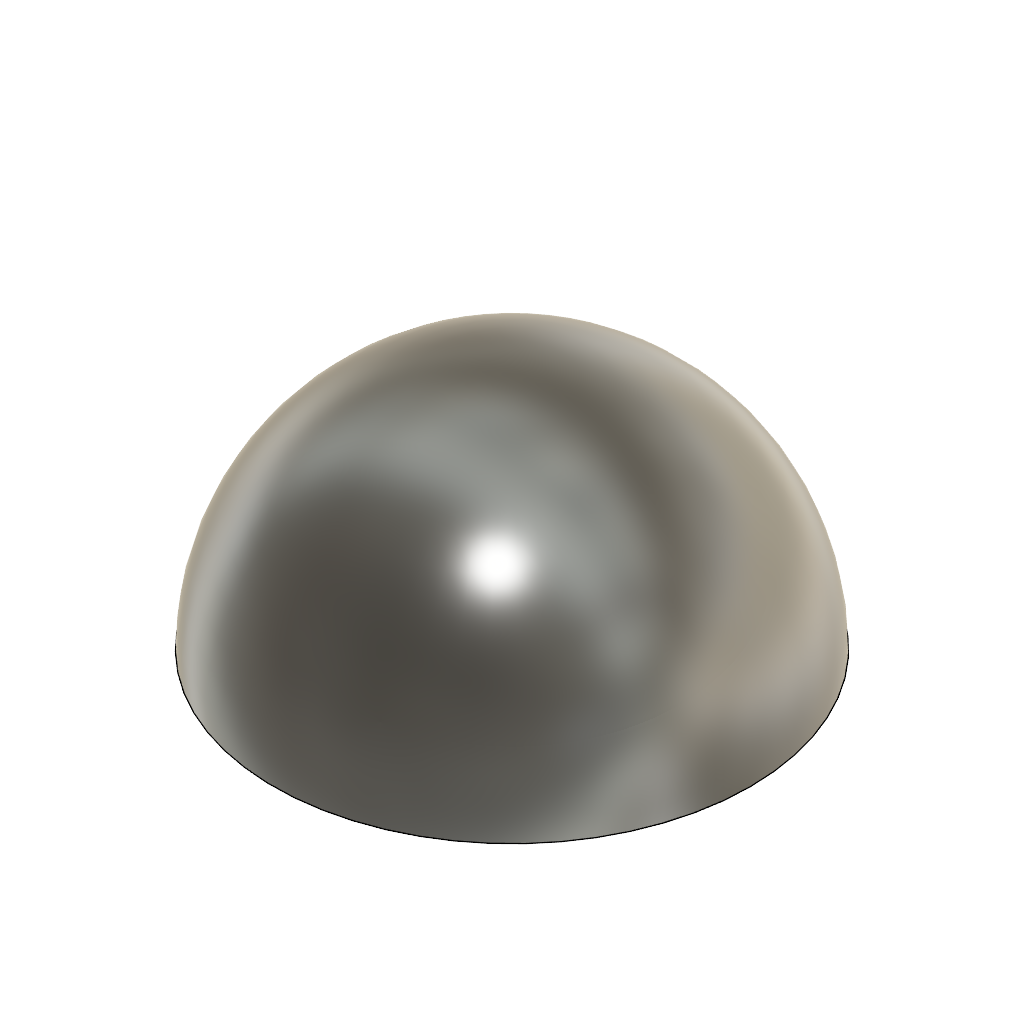
detector de gas v1 (Autodesk Fusion 360 archive; units mm, degrees)
design "capsula"
part number: 2026-10-19-09-24-30-249
Autodesk Fusion 360 part; units mm, degrees
sketch "Boceto1" plane through (0, 0, 0) normal (0, 1, 0) x (1, 0, 0)
  line L0 (0, -44) -> (33, -44)
  arc A0 (0, -77) -> (33, -44) centre (0, -44) ccw
  line L1 (0, -77) -> (0, -44)
  dimension "d1" = 33
  constraint horizontal L0
  constraint coincident L0.start A0.centre
  constraint perpendicular L0 L1
  measures "d1" distance of L0.start L0.end
revolve "Revolución1" add sketch "Boceto1" angle 360 about axis through (0, 0, 77) along (0, 0, -1)
shell "Vaciado1" thickness 3 removed faces 1 at (-17.3436, -1.1549, 44)

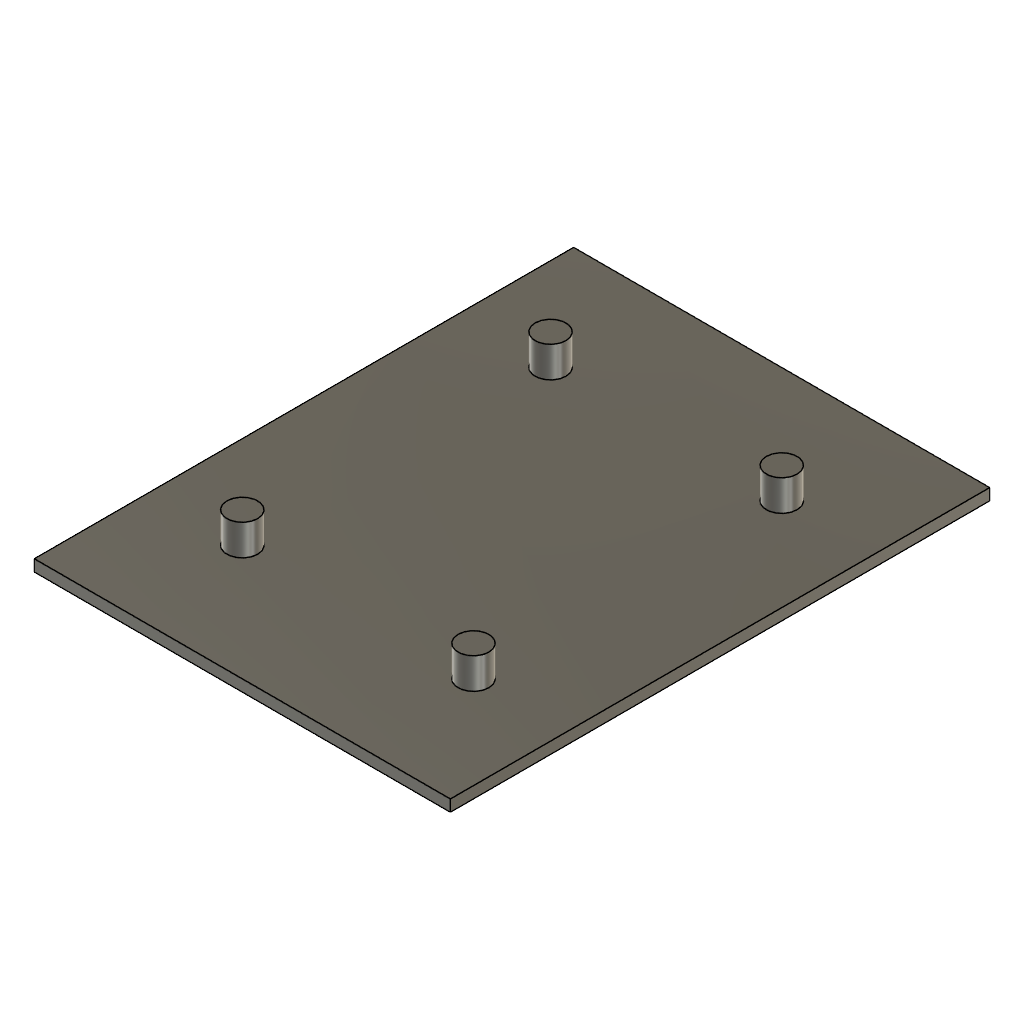
design "base"
part number: 2026-10-19-08-41-53-011
Autodesk Fusion 360 part; units mm, degrees
sketch "Boceto1" plane through (0, 0, 0) normal (0, 0, 1) x (1, 0, 0)
  line L0 (-54, 70) -> (54, 70)
  line L1 (54, 70) -> (54, -70)
  line L2 (54, -70) -> (-54, -70)
  line L3 (-54, -70) -> (-54, 70)
  line L4 (-54, 70) -> (54, -70) construction
  line L5 (54, 70) -> (-54, -70) construction
  dimension "d1" = 108
  dimension "d2" = 140
  constraint horizontal L0
  constraint perpendicular L0 L1
  constraint parallel L0 L2
  constraint parallel L1 L3
  constraint coincident L4 origin
  constraint coincident L5 origin
  measures "d1" distance of L1.end L2.end
  measures "d2" distance of L0.end L1.end
extrude "Extruir1" add sketch "Boceto1" along normal blind 3
sketch "Boceto4" plane through (0, 0, 3) normal (0, 0, 1) x (-1, 0, 0)
  line L0 (54, 70) -> (-54, 70)
  line L1 (-54, 70) -> (-54, -70)
  line L2 (-54, -70) -> (54, -70)
  line L3 (54, -70) -> (54, 70)
  circle A0 centre (30, -40) radius 4
  circle A1 centre (-30, -40) radius 4
  circle A2 centre (30, 40) radius 4
  circle A3 centre (-30, 40) radius 4
  dimension "d9" = 8
  dimension "d10" = 8
  dimension "d11" = 8
  dimension "d12" = 8
  measures "d9" diameter of A0
  measures "d10" diameter of A1
  measures "d11" diameter of A2
  measures "d12" diameter of A3
extrude "Extruir2" add sketch "Boceto4" along normal blind 8 contours A0 | A1 | A2 | A3
